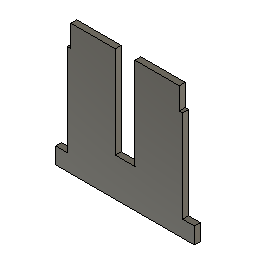
COSO (Autodesk Fusion 360 design; units mm, degrees)
part number: 2026-06-03-16-50-23-530
Autodesk Fusion 360 part; units mm, degrees
sketch "Sketch1" plane through (0, 0, 0) normal (0, 1, 0) x (1, 0, 0)
  line L0 (0, 0) -> (422, 0)
  line L1 (422, 0) -> (422, -50)
  line L2 (0, -50) -> (0, 0)
  line L3 (36, 0) -> (386, 0)
  line L4 (36, -50) -> (36, -330)
  line L5 (36, -330) -> (46, -330)
  line L6 (46, -330) -> (46, -396.35)
  line L7 (46, -396.35) -> (181, -396.35)
  line L8 (386, -50) -> (386, -330)
  line L9 (386, -330) -> (376, -330)
  line L10 (376, -330) -> (376, -396.35)
  line L11 (376, -396.35) -> (241, -396.35)
  line L12 (181, -396.35) -> (181, -116.35)
  line L13 (241, -116.35) -> (241, -396.35)
  line L14 (181, -116.35) -> (241, -116.35)
  line L15 (386, -50) -> (422, -50)
  line L16 (0, -50) -> (36, -50)
  point P0 (36, 0)
  point P1 (386, 0)
  dimension "d2" = 422
  dimension "d3" = 36
  dimension "d4" = 36
  dimension "d5" = 50
  dimension "d7" = 10
  dimension "d10" = 10
  dimension "d11" = 135
  dimension "d12" = 135
  dimension "d15" = 280
  dimension "d16" = 396.35
  dimension "d17" = 396.35
  dimension "d18" = 396.35
  constraint horizontal L0
  constraint vertical L1
  constraint vertical L2
  constraint coincident L0.start L2.end
  constraint coincident L0 P0
  constraint coincident L0 P1
  constraint coincident P0 L3.start
  constraint coincident P1 L3.end
  constraint perpendicular L4 L5
  constraint perpendicular L5 L6
  constraint perpendicular L6 L7
  constraint perpendicular L5 L8
  constraint perpendicular L8 L9
  constraint perpendicular L5 L10
  constraint perpendicular L10 L11
  constraint perpendicular L11 L13
  constraint perpendicular L13 L14
  constraint perpendicular L1 L15
  constraint perpendicular L4 L16
  measures "d2" distance of L0.start L0.end
  measures "d3" distance of L0.start L3.start
  measures "d4" distance of L0.end P1
  measures "d5" distance of P0 L4.start
  measures "d7" distance of L4.end L5.end
  measures "d10" distance of L8.end L9.end
  measures "d11" distance of L6.end L7.end
  measures "d12" distance of L10.end L11.end
  measures "d15" distance of L7.end L12.end
  measures "d16" distance of L0 L11
  measures "d17" distance of L3 L7
  measures "d18" distance of L3 L7
extrude "Extrude1" add sketch "Sketch1" along normal blind 18
